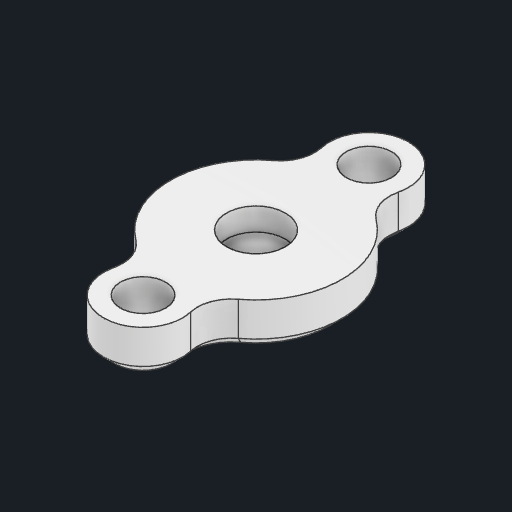
# Autodesk Inventor part: Y-axis end
Saved by Autodesk Inventor 2026.2 (Build 302298010, 298A)
## iProperties
Created: 2026-04-26
Part Number: Y-axis end
Material: PBT 플라스틱
Document SubType Name: Modeling
Designer: work
Density: 1.31 g/cm^3
Appearance: 매끄러움 - 흰색
Author: work
Autodesk Inventor part; units mm, degrees
ref_plane "YZ Plane" through (0, 0, 0) normal (1, 0, 0) x (0, 1, 0)
ref_plane "XZ Plane" through (0, 0, 0) normal (0, 1, 0) x (-1, 0, 0)
ref_plane "XY Plane" through (0, 0, 0) normal (0, 0, 1) x (1, 0, 0)
sketch "스케치1" plane through (0, 0, 0) normal (0, 1, 0) x (-1, 0, 0)
  circle A0 centre (0, 0) radius 7.6
  line L0 (0, 10) -> (0, -10)
  circle A1 centre (0, 10) radius 2
  circle A2 centre (0, -10) radius 2
  circle A3 centre (0, 10) radius 3.5
  circle A4 centre (0, -10) radius 3.5
  point P0 (-2.1971, 7.2755)
  point P1 (-2.1971, -7.2755)
  point P2 (2.1971, -7.2755)
  point P3 (2.1971, 7.2755)
  dimension "d0" = 20
  dimension "d1" = 4
  dimension "d2" = 4
  dimension "d3" = 7
  dimension "d4" = 7
  dimension "d5" = 15.2
  constraints: 5 centre point, 5 coincident, 2 end point, 1 midpoint, 1 vertical
  measures "d0" distance of L0.start L0.end
  measures "d1" diameter of A1
  measures "d2" diameter of A2
  measures "d3" diameter of A3
  measures "d4" diameter of A4
  measures "d5" diameter of A0
extrude "돌출1" add sketch "스케치1" along normal blind 4
sketch "스케치2" plane through (0, 4, 0) normal (0, 1, 0) x (1, 0, 0)
  circle A0 centre (0, 0) radius 2.6
  dimension "d8" = 5.2
  constraints: 1 centre point, 1 coincident
  measures "d8" diameter of A0
extrude "돌출2" cut sketch "스케치2" against normal blind 2
fillet "모깎기1" radius 3 4 edges at (2.1971, 2, 7.2755) (-2.1971, 2, -7.2755) (2.1971, 2, -7.2755) (-2.1971, 2, 7.2755)
chamfer "모따기1" distance 1 angle 45 4 edges at (-7.6, 0, 0) (0, 0, 13.5) (7.6, 0, 0) (0, 0, -13.5)
